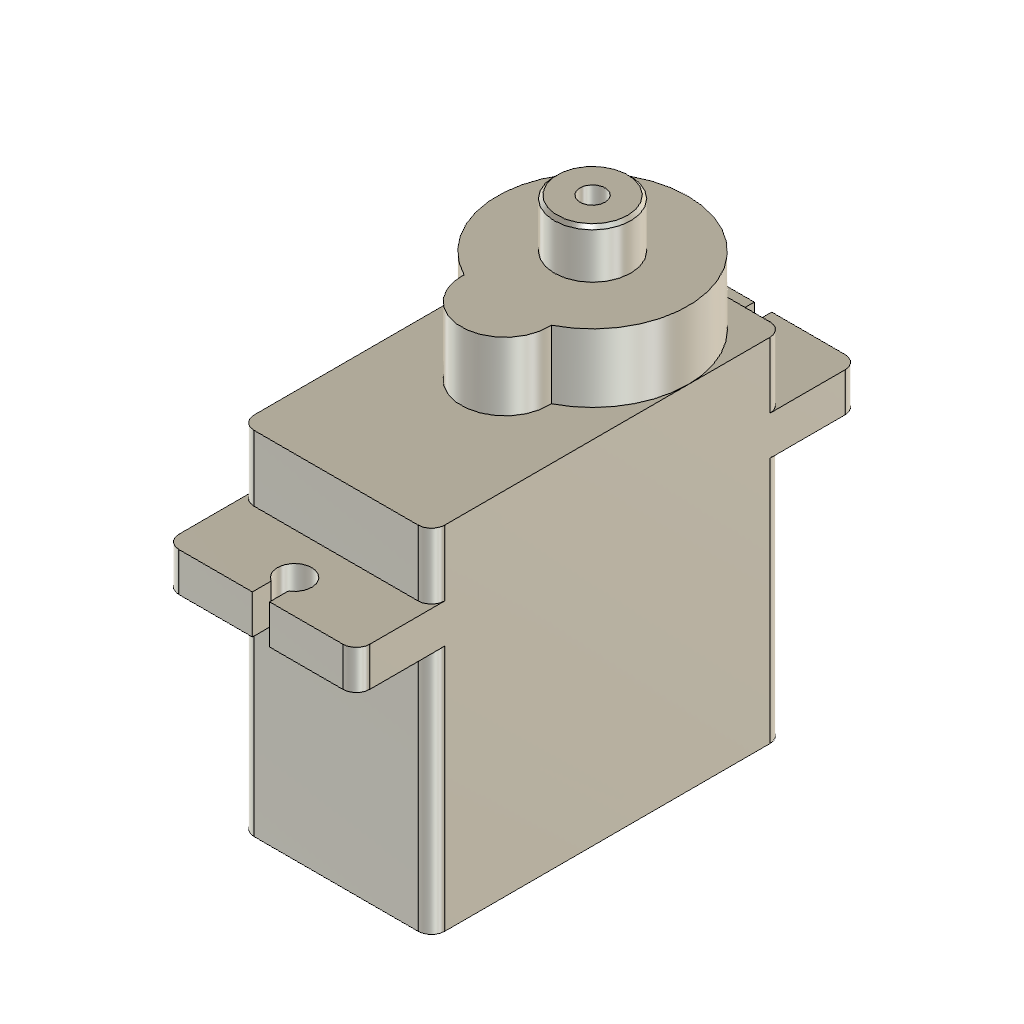
SG90 native (Autodesk Fusion 360 design; units mm, degrees)
part number: 2026-10-14-09-23-27-464
Autodesk Fusion 360 part; units mm, degrees
ref_plane "WorkPlane1" through (0, 0, -11.25) normal (0, 0, 1) x (1, 0, 0)
sketch "Case" plane through (0, 0, -11.25) normal (0, 0, 1) x (1, 0, 0)
  line L0 (6.1, -15.55) -> (6.1, 5.25)
  arc A0 (6.1, 5.25) -> (5.25, 6.1) centre (5.25, 5.25) ccw
  line L1 (5.25, 6.1) -> (-5.25, 6.1)
  arc A1 (-5.25, 6.1) -> (-6.1, 5.25) centre (-5.25, 5.25) ccw
  line L2 (-6.1, 5.25) -> (-6.1, -15.55)
  arc A2 (-6.1, -15.55) -> (-5.25, -16.4) centre (-5.25, -15.55) ccw
  line L3 (-5.25, -16.4) -> (5.25, -16.4)
  arc A3 (5.25, -16.4) -> (6.1, -15.55) centre (5.25, -15.55) ccw
  dimension "d34" = 0.85
  dimension "d35" = 5.25
  dimension "d36" = 5.25
  dimension "d37" = 5.25
  dimension "d38" = 15.55
  constraint vertical L0
  constraint horizontal L1
  constraint vertical L2
  constraint horizontal L3
  constraint tangent L0 A3
  constraint tangent L0 A0
  constraint tangent A0 L1
  constraint tangent L1 A1
  constraint tangent A1 L2
  constraint tangent L2 A2
  constraint tangent A2 L3
  constraint tangent L3 A3
  constraint equal A0 A1
  constraint equal A0 A2
  constraint equal A0 A3
  measures "d34" radius of A0
  measures "d35" horizontal distance of origin A0.centre
  measures "d36" vertical distance of origin A0.centre
  measures "d37" horizontal distance of origin A1.centre
  measures "d38" vertical distance of origin A2.centre
extrude "Case (1)" add sketch "Case" along normal mid plane 22.5
ref_plane "WorkPlane2" through (0, 0, -5.45) normal (0, 0, 1) x (1, 0, 0)
sketch "Tabs" plane through (0, 0, -5.45) normal (0, 0, 1) x (1, 0, 0)
  line L0 (6.1, -20.35) -> (6.1, 10.05)
  arc A0 (6.1, 10.05) -> (5.25, 10.9) centre (5.25, 10.05) ccw
  line L1 (5.25, 10.9) -> (-5.25, 10.9)
  arc A1 (-5.25, 10.9) -> (-6.1, 10.05) centre (-5.25, 10.05) ccw
  line L2 (-6.1, 10.05) -> (-6.1, -20.35)
  arc A2 (-6.1, -20.35) -> (-5.25, -21.2) centre (-5.25, -20.35) ccw
  line L3 (-5.25, -21.2) -> (5.25, -21.2)
  arc A3 (5.25, -21.2) -> (6.1, -20.35) centre (5.25, -20.35) ccw
  dimension "d39" = 0.85
  dimension "d40" = 5.25
  dimension "d41" = 10.05
  dimension "d42" = 5.25
  dimension "d43" = 20.35
  constraint vertical L0
  constraint horizontal L1
  constraint vertical L2
  constraint horizontal L3
  constraint tangent L0 A3
  constraint tangent L0 A0
  constraint tangent A0 L1
  constraint tangent L1 A1
  constraint tangent A1 L2
  constraint tangent L2 A2
  constraint tangent A2 L3
  constraint tangent L3 A3
  constraint equal A0 A1
  constraint equal A0 A2
  constraint equal A0 A3
  measures "d39" radius of A0
  measures "d40" horizontal distance of origin A0.centre
  measures "d41" vertical distance of origin A0.centre
  measures "d42" horizontal distance of origin A1.centre
  measures "d43" vertical distance of origin A2.centre
extrude "Tabs (1)" add sketch "Tabs" along normal mid plane 2.5
ref_plane "WorkPlane3" through (0, 0, -5.45) normal (0, 0, 1) x (1, 0, 0)
sketch "Back tab hole" plane through (0, 0, -5.45) normal (0, 0, 1) x (1, 0, 0)
  line L0 (0.55, -21.55) -> (0.55, -20.0026)
  arc A0 (0.55, -20.0026) -> (-0.55, -20.0026) centre (0, -19.05) ccw
  line L1 (-0.55, -20.0026) -> (-0.55, -21.55)
  line L2 (-0.55, -21.55) -> (0.55, -21.55)
  dimension "d44" = 1.1
  dimension "d45" = 19.05
  dimension "d46" = 0.55
  dimension "d47" = 21.55
  dimension "d48" = 0.55
  constraint vertical L0
  constraint vertical L1
  constraint horizontal L2
  constraint vertical origin A0.centre
  measures "d44" radius of A0
  measures "d45" vertical distance of origin A0.centre
  measures "d46" horizontal distance of origin L0.start
  measures "d47" vertical distance of origin L0.start
  measures "d48" horizontal distance of origin A0.end
extrude "Back tab hole (1)" cut sketch "Back tab hole" along normal mid plane 3.5
ref_plane "WorkPlane4" through (0, 0, -5.45) normal (0, 0, 1) x (1, 0, 0)
sketch "Front tab hole" plane through (0, 0, -5.45) normal (0, 0, 1) x (1, 0, 0)
  line L0 (-0.55, 11.25) -> (-0.55, 9.7026)
  arc A0 (-0.55, 9.7026) -> (0.55, 9.7026) centre (0, 8.75) ccw
  line L1 (0.55, 9.7026) -> (0.55, 11.25)
  line L2 (0.55, 11.25) -> (-0.55, 11.25)
  dimension "d49" = 1.1
  dimension "d50" = 8.75
  dimension "d51" = 0.55
  dimension "d52" = 11.25
  dimension "d53" = 0.55
  constraint vertical L0
  constraint vertical L1
  constraint horizontal L2
  constraint vertical origin A0.centre
  measures "d49" radius of A0
  measures "d50" vertical distance of origin A0.centre
  measures "d51" horizontal distance of origin L0.start
  measures "d52" vertical distance of origin L0.start
  measures "d53" horizontal distance of origin A0.end
extrude "Front tab hole (1)" cut sketch "Front tab hole" along normal mid plane 3.5
ref_plane "WorkPlane5" through (0, 0, 2.175) normal (0, 0, 1) x (1, 0, 0)
sketch "Tower" plane through (0, 0, 2.175) normal (0, 0, 1) x (1, 0, 0)
  circle A0 centre (0, 0) radius 6.1
  dimension "d54" = 12.2
  constraint coincident A0.centre origin
  measures "d54" diameter of A0
extrude "Tower (1)" add sketch "Tower" along normal mid plane 4.35
ref_plane "WorkPlane6" through (0, 0, 2.175) normal (0, 0, 1) x (1, 0, 0)
sketch "Tower boss" plane through (0, 0, 2.175) normal (0, 0, 1) x (1, 0, 0)
  circle A0 centre (0, -5.6) radius 2.8
  dimension "d55" = 5.6
  dimension "d56" = 5.6
  constraint vertical origin A0.centre
  measures "d55" diameter of A0
  measures "d56" vertical distance of origin A0.centre
extrude "Tower boss (1)" add sketch "Tower boss" along normal mid plane 4.35
sketch "Shaft" plane through (0, 0, 0) normal (0, 1, 0) x (1, 0, 0)
  line L0 (0, -4.35) -> (2.45, -4.35)
  line L1 (2.45, -4.35) -> (2.45, -7.25)
  line L2 (2.45, -7.25) -> (2.25, -7.45)
  line L3 (2.25, -7.45) -> (0, -7.45)
  line L4 (0, -7.45) -> (0, -4.35)
  line L5 (0, -4.35) -> (0, -7.45) construction
  dimension "d57" = 4.35
  dimension "d58" = 2.45
  dimension "d59" = 7.25
  dimension "d60" = 2.25
  dimension "d61" = 7.45
  dimension "d62" = 4.35
  dimension "d63" = 7.45
  constraint horizontal L0
  constraint vertical L1
  constraint horizontal L3
  constraint vertical L4
  constraint vertical L5
  constraint vertical origin L0.start
  measures "d57" vertical distance of origin L0.start
  measures "d58" horizontal distance of origin L0.end
  measures "d59" vertical distance of origin L1.end
  measures "d60" horizontal distance of origin L2.end
  measures "d61" vertical distance of origin L2.end
  measures "d62" vertical distance of origin L0.start
  measures "d63" vertical distance of origin L3.end
revolve "Shaft (1)" add sketch "Shaft" angle 360 about axis through (0, 0, 4.35) along (0, 0, 1)
ref_plane "WorkPlane7" through (0, 0, 4.025) normal (0, 0, 1) x (1, 0, 0)
sketch "Horn screw hole" plane through (0, 0, 4.025) normal (0, 0, 1) x (1, 0, 0)
  circle A0 centre (0, 0) radius 0.8
  dimension "d64" = 1.6
  constraint coincident A0.centre origin
  measures "d64" diameter of A0
extrude "Horn screw hole (1)" cut sketch "Horn screw hole" along normal mid plane 7.85
ref_plane "WorkPlane8" through (0, 5.6, 0) normal (0, 1, 0) x (0, 0, 1)
sketch "Cable stub" plane through (0, 5.6, 0) normal (0, 1, 0) x (1, 0, 0)
  line L0 (-1, 18) -> (1, 18)
  arc A0 (1, 17) -> (1, 18) centre (1, 17.5) ccw
  line L1 (1, 17) -> (-1, 17)
  arc A1 (-1, 18) -> (-1, 17) centre (-1, 17.5) ccw
  dimension "d65" = 0.5
  dimension "d66" = 1
  dimension "d67" = 17.5
  dimension "d68" = 1
  constraint horizontal L0
  constraint horizontal L1
  constraint tangent L0 A1
  constraint tangent L0 A0
  constraint tangent A0 L1
  constraint tangent L1 A1
  measures "d65" radius of A0
  measures "d66" horizontal distance of origin A0.centre
  measures "d67" vertical distance of origin A0.centre
  measures "d68" horizontal distance of origin A1.centre
extrude "Cable stub (1)" add sketch "Cable stub" along normal mid plane 3
named bodies: "SG90 native"
